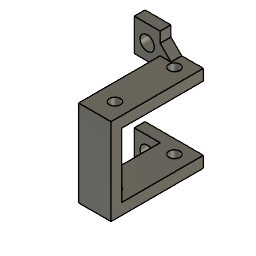
Yellow Motor Mount (Autodesk Fusion 360 design; units mm, degrees)
Autodesk Fusion 360 part; units mm, degrees
sketch "Sketch1" plane through (0, 0, 0) normal (0, 0, 1) x (1, 0, 0)
  line L0 (0, 0) -> (9.525, 0)
  line L1 (9.525, 0) -> (9.525, 27.1272)
  line L2 (9.525, 27.1272) -> (0, 27.1272)
  line L3 (0, 27.1272) -> (0, 0)
  circle A0 centre (5.0144, 5.675) radius 1.6
  circle A1 centre (5.0144, 23.1329) radius 1.6
  dimension "d1" = 3.2
  dimension "d2" = 3.2
  dimension "d3" = 17.4579
  dimension "d4" = 5.0144
  dimension "d5" = 5.675
  dimension "d6" = 9.525
  dimension "d7" = 27.1272
  constraint horizontal L0
  constraint vertical L1
  constraint horizontal L2
  constraint vertical L3
  constraint coincident L0.start L3.end
  constraint vertical A0.centre A1.centre
  measures "d1" diameter of A1
  measures "d2" diameter of A0
  measures "d3" distance of A0.centre A1.centre
  measures "d4" distance of L3 A1.centre
  measures "d5" distance of L0 A0.centre
  measures "d6" distance of L1 L3
  measures "d7" distance of L0 L2
extrude "Extrude1" add sketch "Sketch1" along normal blind 25.4
sketch "Sketch2" plane through (0, 0, 0) normal (-1, 0, 0) x (0, -1, 0)
  line L0 (-27.1272, 0) -> (0, 0)
  line L1 (0, 0) -> (0, 25.4)
  line L2 (0, 25.4) -> (-27.1272, 25.4)
  line L3 (-27.1272, 25.4) -> (-27.1272, 0)
  line L4 (-3.175, 3.302) -> (-27.1272, 3.302)
  line L5 (-27.1272, 3.302) -> (-27.1272, 22.1488)
  line L6 (-27.1272, 22.1488) -> (-3.175, 22.1488)
  line L7 (-3.175, 22.1488) -> (-3.175, 3.302)
  line L8 (-24.5872, 25.4) -> (-27.1272, 25.4)
  line L9 (-27.1272, 25.4) -> (-27.1272, 34.925)
  line L10 (-27.1272, 34.925) -> (-24.5872, 34.925)
  line L11 (-24.5872, 34.925) -> (-24.5872, 25.4)
  line L12 (-27.1272, 0) -> (-24.5872, 0)
  line L13 (-24.5872, 0) -> (-24.5872, -9.525)
  line L14 (-24.5872, -9.525) -> (-27.1272, -9.525)
  line L15 (-27.1272, -9.525) -> (-27.1272, 0)
  dimension "d11" = 3.302
  dimension "d12" = 18.8468
  dimension "d16" = 3.175
  dimension "d17" = 2.54
  dimension "d18" = 2.54
  dimension "d19" = 9.525
  dimension "d20" = 9.525
  constraint horizontal L4
  constraint vertical L5
  constraint horizontal L6
  constraint vertical L7
  constraint coincident L3 L5.end
  constraint horizontal L8
  constraint vertical L9
  constraint horizontal L10
  constraint vertical L11
  constraint coincident L2 L8.start
  constraint horizontal L12
  constraint vertical L13
  constraint horizontal L14
  constraint vertical L15
  constraint coincident L0.start L3.end
  constraint coincident L2.end L3.start
  measures "d11" distance of L0 L4
  measures "d12" distance of L4 L6
  measures "d16" distance of L1 L7
  measures "d17" distance of L9 L11
  measures "d18" distance of L13 L15
  measures "d19" distance of L8.start L10.end
  measures "d20" distance of L12.end L13.end
extrude "Extrude2" cut sketch "Sketch2" against normal blind 9.525 contours L3 L4 L5 L6 L7
sketch "Sketch3" plane through (0, 0, 0) normal (-1, 0, 0) x (0, -1, 0)
  line L0 (-3.175, 22.1488) -> (-3.175, 3.302)
  line L1 (-3.175, 3.302) -> (-27.1272, 3.302)
  line L2 (-27.1272, 3.302) -> (-27.1272, 0)
  line L3 (-27.1272, 0) -> (0, 0)
  line L4 (0, 0) -> (0, 25.4)
  line L5 (-27.1272, 3.302) -> (-23.9522, 3.302)
  line L6 (-23.9522, 3.302) -> (-23.9522, -6.223)
  line L7 (-23.9522, -6.223) -> (-27.1272, -6.223)
  line L8 (-27.1272, -6.223) -> (-27.1272, 3.302)
  line L9 (-27.1272, 22.1488) -> (-23.9522, 22.1488)
  line L10 (-23.9522, 22.1488) -> (-23.9522, 31.6738)
  line L11 (-23.9522, 31.6738) -> (-27.1272, 31.6738)
  line L12 (-27.1272, 31.6738) -> (-27.1272, 22.1488)
  point P0 (-27.1272, 22.1488)
  dimension "d23" = 3.175
  dimension "d24" = 9.525
  dimension "d26" = 9.525
  dimension "d27" = 3.175
  constraint horizontal L5
  constraint vertical L6
  constraint horizontal L7
  constraint vertical L8
  constraint coincident L1.end L2.start
  constraint horizontal L9
  constraint vertical L10
  constraint horizontal L11
  constraint vertical L12
  constraint coincident P0 L9.start
  measures "d23" distance of L6.end L7.end
  measures "d24" distance of L1.end L7.end
  measures "d26" distance of P0 L11.end
  measures "d27" distance of P0 L9.end
extrude "Extrude4" add sketch "Sketch3" along normal blind 7.62
chamfer "Chamfer1" distance 3.175 angle 45 2 edges at (0, 25.5397, 25.4) (0, 25.5397, 0) tangent chain off
sketch "Sketch4" plane through (0, 27.1272, 0) normal (0, 1, 0) x (-1, 0, 0)
  line L0 (-9.525, 22.1488) -> (7.62, 22.1488)
  line L1 (7.62, 22.1488) -> (7.62, 31.6738)
  line L2 (7.62, 31.6738) -> (0, 31.6738)
  line L3 (0, 31.6738) -> (0, 28.575)
  line L4 (0, 28.575) -> (-3.175, 25.4)
  line L5 (-3.175, 25.4) -> (-9.525, 25.4)
  line L6 (-9.525, 25.4) -> (-9.525, 22.1488)
  circle A0 centre (3.81, 26.7254) radius 2.1
  circle A1 centre (3.81, -1.2746) radius 2.1
  line L7 (3.81, 26.7254) -> (3.81, 31.6738)
  line L8 (3.81, -1.2746) -> (3.81, -6.223)
  line L9 (0, -6.223) -> (7.62, -6.223)
  dimension "d31" = 4.2
  dimension "d32" = 4.2
  dimension "d33" = 28
  dimension "d34" = 3.81
  constraint vertical A0.centre A1.centre
  constraint coincident A0.centre L7.start
  constraint midpoint L2 L7.end
  constraint coincident A1.centre L8.start
  constraint vertical L8
  constraint equal L7 L8
  constraint coincident L8.end L9
  measures "d31" diameter of A1
  measures "d32" diameter of A0
  measures "d33" distance of A0.centre A1.centre
  measures "d34" distance of L1 A0.centre
extrude "Extrude5" cut sketch "Sketch4" against normal blind 3.175 contours A0 | A1
equation "d5 = 2.5 mm + 0.125 in"
equation "d6 = ( 3 / 8 ) * 1 in"
equation "d7 = 0.943 in + 0.125 in"
equation "d11 = ( 1 - 0.74 ) / 2 * 1 in"
equation "d19 = ( 3 / 8 ) * 1 in"
equation "d20 = ( 3 / 8 ) * 1 in"
equation "d24 = ( 3 / 8 ) * 1 in"
equation "d26 = ( 3 / 8 ) * 1 in"
